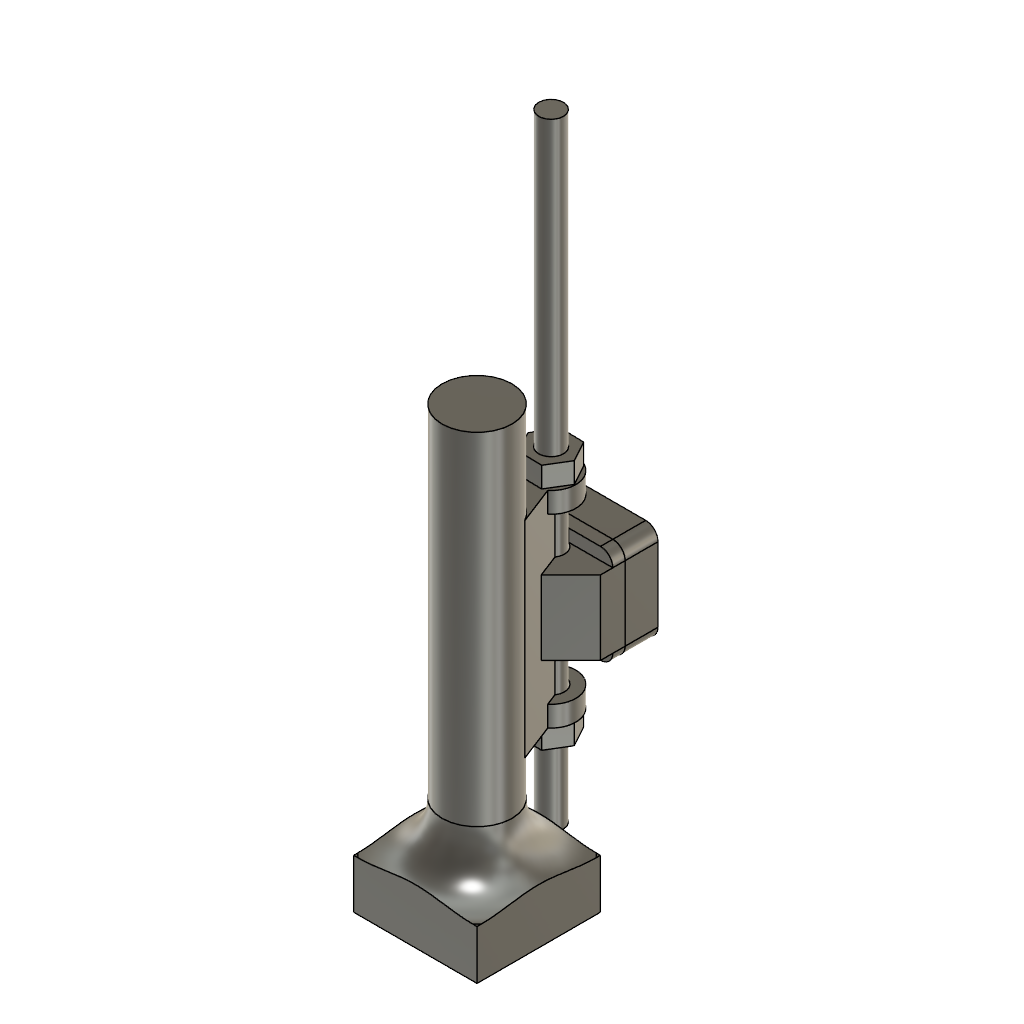
焼き印マシーンステー (Autodesk Fusion 360 design; units mm, degrees)
part number: 2026-09-23-19-43-58-158
Autodesk Fusion 360 part; units mm, degrees
cylinder "円柱プリミティブ1" add diameter 6 height 150 placed x (1, 0, 0) y (0, 1, 0) z (0, 0, 1) at (0, 0, 0) makes body 1
sketch "スケッチ2" plane through (0, 0, 0) normal (0, 0, 1) x (1, 0, 0)
  circle A0 centre (0, -20) radius 8.5
  line L0 (15, -35) -> (-15, -35)
  line L1 (-15, -35) -> (-15, -5)
  line L2 (-15, -5) -> (15, -5)
  line L3 (15, -5) -> (15, -35)
  line L4 (15, -35) -> (-15, -5) construction
  line L5 (-15, -35) -> (15, -5) construction
  point P0 (0, -20)
  dimension "d4" = 17
  dimension "d5" = 30
  dimension "d6" = 30
  constraint horizontal L0
  constraint perpendicular L0 L1
  constraint parallel L0 L2
  constraint parallel L1 L3
  constraint coincident L4 P0
  constraint coincident L5 P0
  constraint coincident P0 A0.centre
  measures "d4" diameter of A0
  measures "d5" distance of L1.end L2.end
  measures "d6" distance of L0.end L1.end
extrude "押し出し1" add sketch "スケッチ2" along normal blind 95 separate body contours A0 makes body 2
extrude "押し出し2" add sketch "スケッチ2" against normal blind 12 contours A0 | L0 L1 L2 L3 bodies 2
fillet "フィレット1" radius 12 1 edges at (-7.9248, -23.0737, 0) on bodies 2
sketch "スケッチ3" plane through (0, 0, 0) normal (0, 1, 0) x (1, 0, 0)
  line L0 (-47, -50) -> (-29, -50)
  line L1 (-26, -47) -> (-26, -29)
  line L2 (-29, -26) -> (-47, -26)
  line L3 (-50, -29) -> (-50, -47)
  arc A0 (-47, -26) -> (-50, -29) centre (-47, -29) ccw
  arc A1 (-26, -29) -> (-29, -26) centre (-29, -29) ccw
  arc A2 (-29, -50) -> (-26, -47) centre (-29, -47) ccw
  arc A3 (-50, -47) -> (-47, -50) centre (-47, -47) ccw
  line L4 (-38, -38) -> (-46, -38)
  circle A4 centre (-46, -38) radius 2.4
  line L5 (-38, -38) -> (-38, -30)
  circle A5 centre (-30, -38) radius 2.4
  point P0 (-50, -50)
  point P1 (-26, -50)
  point P2 (-50, -26)
  dimension "d13" = 24
  dimension "d14" = 24
  dimension "d15" = 3
  dimension "d16" = 8
  dimension "d17" = 4.8
  constraint horizontal L0
  constraint vertical L1
  constraint horizontal L2
  constraint vertical L3
  constraint coincident P2 L3
  constraint coincident P2 L2
  constraint tangent L3 A0
  constraint tangent L2 A0
  constraint tangent L2 A1
  constraint tangent L1 A1
  constraint equal A0 A1
  constraint coincident P1 L1
  constraint coincident P1 L0
  constraint tangent L1 A2
  constraint tangent L0 A2
  constraint equal A0 A2
  constraint coincident P0 L0
  constraint coincident P0 L3
  constraint tangent L0 A3
  constraint tangent L3 A3
  constraint equal A0 A3
  constraint perpendicular L3 L4
  constraint coincident L4.end A4.centre
  constraint perpendicular L4 L5
  constraint symmetric A4 L5 A5
  measures "d13" distance of P0 P1
  measures "d14" distance of P0 P2
  measures "d15" radius of A0
  measures "d16" distance of L4.start L4.end
  measures "d17" diameter of A4
extrude "押し出し3" add sketch "スケッチ3" along normal blind 8 separate body makes body 3
move_body "移動1" bodies 2 to x (1, 0, 0) y (0, 1, 0) z (0, 0, 1) at (0, 2, 12)
move_body "移動2" bodies 2 1 to x (1, 0, 0) y (0, 1, 0) z (0, 0, 1) at (0, 0, -24)
sketch "スケッチ4" plane through (0, 0, 0) normal (0, 0, 1) x (1, 0, 0)
  line L0 (-2.7688, 5.0663) -> (-5.7719, 0.1353)
  line L1 (-5.7719, 0.1353) -> (-3.0032, -4.931)
  line L2 (-3.0032, -4.931) -> (2.7688, -5.0663)
  line L3 (2.7688, -5.0663) -> (5.7719, -0.1353)
  line L4 (5.7719, -0.1353) -> (3.0032, 4.931)
  line L5 (3.0032, 4.931) -> (-2.7688, 5.0663)
  circle A0 centre (0, 0) radius 3
  dimension "d20" = 5
  dimension "d21" = 6
  constraint coincident A0.centre origin
  measures "d20" distance of A0.centre L5
  measures "d21" diameter of A0
extrude "押し出し4" add sketch "スケッチ4" along normal blind 5 separate body makes body 4
copy_body "ボディのコピーと貼り付け1" bodies 4 makes body 5
move_body "移動3" bodies 5 to x (1, 0, 0) y (0, 1, 0) z (0, 0, 1) at (0, 0, 55)
move_body "移動4" bodies 5 4 to x (1, 0, 0) y (0, 1, 0) z (0, 0, 1) at (0, 0, -5)
move_body "移動5" bodies 2 to x (1, 0, 0) y (0, 1, 0) z (0, 0, 1) at (0, 0, -10)
sketch "スケッチ5" plane through (0, 0, 0) normal (0, 0, 1) x (1, 0, 0)
  circle A0 centre (0, 0) radius 3
  circle A1 centre (0, 0) radius 3
  line L0 (0, 0) -> (0, -18)
  circle A2 centre (0, -18) radius 8.5
  line L1 (0, 0) -> (-2.5981, -1.5)
  line L2 (0, 0) -> (3, 0) construction
  line L3 (0, -18) -> (0, -9.5)
  line L4 (-7.3612, -13.75) -> (0, -18)
  line L5 (-2.5981, -1.5) -> (-7.3612, -13.75)
  line L6 (2.5981, -1.5) -> (7.3612, -13.75)
  circle A3 centre (0, 0) radius 6
  dimension "d24" = 6
  dimension "d25" = 18
  dimension "d26" = 150
  dimension "d27" = 120
  dimension "d28" = 12
  constraint coincident A0.centre A1.centre
  constraint vertical L0
  constraint coincident L0.end A2.centre
  constraint horizontal L2
  constraint coincident A1 L1.end
  constraint coincident A2 L3.end
  constraint coincident A2 L4.start
  constraint symmetric L1.end L3 L6.start
  constraint symmetric L3 L4.start L6.end
  measures "d24" diameter of A0
  measures "d25" distance of A0.centre L0.end
  measures "d26" angle of L1 L2
  measures "d27" angle of L1 L3
  measures "d28" diameter of A3
extrude "押し出し5" add sketch "スケッチ5" along normal blind 50 separate body contours A0 A1 L0 L5 A3 | A0 A1 L0 L6 A3 | L0 A2 L5 A3 | L0 A2 L6 A3 makes body 6
extrude "押し出し6" add sketch "スケッチ5" along normal blind 5 separate body contours A0 A1 L5 L6 A3 | A0 A1 L0 L5 A3 | A0 A1 L0 L6 A3 makes body 7
copy_body "ボディのコピーと貼り付け2" bodies 7 makes body 8
move_body "移動6" bodies 8 to x (1, 0, 0) y (0, 1, 0) z (0, 0, 1) at (0, 0, 40)
move_body "移動7" bodies 3 to x (1, 0, 0) y (0, 1, 0) z (0, 0, 1) at (38, 6, -13)
move_body "移動8" bodies 8 to x (1, 0, 0) y (0, 1, 0) z (0, 0, 1) at (0, 0, 5)
sketch "スケッチ6" plane through (0, 6, 0) normal (0, -1, 0) x (1, 0, 0)
  circle A0 centre (8, 25) radius 2.4
  circle A1 centre (-8, 25) radius 2.4
  arc A2 (-9, 37) -> (-12, 34) centre (-9, 34) ccw
  line L0 (-12, 34) -> (-12, 16)
  arc A3 (-12, 16) -> (-9, 13) centre (-9, 16) ccw
  line L1 (-9, 13) -> (9, 13)
  arc A4 (9, 13) -> (12, 16) centre (9, 16) ccw
  line L2 (12, 16) -> (12, 34)
  arc A5 (12, 34) -> (9, 37) centre (9, 34) ccw
  line L3 (9, 37) -> (-9, 37)
  circle A6 centre (-8, 25) radius 1.9
  circle A7 centre (8, 25) radius 1.9
  dimension "d33" = -0.5
  dimension "d34" = -0.5
extrude "押し出し7" add sketch "スケッチ6" along normal blind 3 separate body contours A0 | A1 | A2 L0 A3 L1 A4 L2 A5 L3 | A6 | A7 makes body 9
extrude "押し出し8" add sketch "スケッチ6" against normal blind 8 contours A6 | A7 bodies 9
ref_plane "作業平面1" through (0, 0, 16) normal (0, 0, 1) x (1, 0, 0)
sketch "スケッチ7" plane through (0, 0, 16) normal (0, 0, 1) x (1, 0, 0)
  line L0 (-12, 3) -> (12, 3)
  line L1 (12, 3) -> (12, 0)
  line L2 (12, 0) -> (-12, 0)
  line L3 (-12, 0) -> (-12, 3)
  circle A0 centre (0, -18) radius 8.5
  line L4 (-12, 0) -> (0, -12)
  line L5 (0, -12) -> (12, 0)
  circle A1 centre (0, 0) radius 3
  dimension "d41" = 17
  constraint horizontal L0
  constraint vertical L1
  constraint horizontal L2
  constraint vertical L3
  constraint perpendicular L4 L5
  constraint coincident A1.centre origin
  measures "d41" diameter of A0
extrude "押し出し9" add sketch "スケッチ7" along normal blind 18 separate body contours L0 L2 L3 A1 | L0 L1 L2 A1 | L2 A0 L4 L5 A1 makes body 10
combine "結合1" operation add target body 6 tool bodies 10 9 8 7
sketch "スケッチ8" plane through (0, 0, 50) normal (0, 0, 1) x (-1, 0, 0)
  circle A0 centre (0, 0) radius 3
  arc A1 (-3.8154, 4.6307) -> (3.8154, 4.6307) centre (0, 0) ccw
  line L0 (3.8154, 4.6307) -> (7.3612, 13.75)
  arc A2 (-7.3612, 13.75) -> (7.3612, 13.75) centre (0, 18) ccw
  line L1 (-7.3612, 13.75) -> (-3.8154, 4.6307)
  circle A3 centre (0, 0) radius 3.25
  dimension "d44" = 6.5
  constraint coincident A0.centre A1.centre
  measures "d44" diameter of A3
extrude "押し出し10" cut sketch "スケッチ8" against normal blind 55 contours A3 bodies 6
named bodies: "寸切り", "はんだごて", "ToF", "ナット", "ナット (1)", "ステー"
